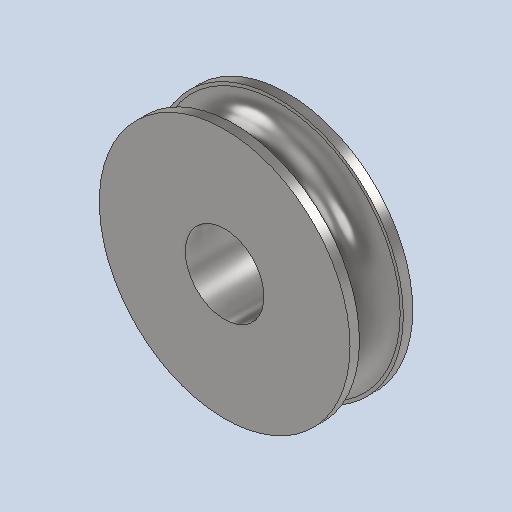
# Autodesk Inventor part: Biegerolle 62
Saved by Autodesk Inventor 2027.1 (Build 311270010, 270A)
## iProperties
Created: 2026-07-29
Part Number: Biegerolle 62
Material: Stahl, Legierung
Document SubType Name: Modeling
Designer: moest
Density: 7.73 g/cm^3
Appearance: Halbpoliert
Author: moest
Autodesk Inventor part; units mm, degrees
ref_plane "YZ Plane" through (0, 0, 0) normal (1, 0, 0) x (0, 1, 0)
ref_plane "XZ Plane" through (0, 0, 0) normal (0, 1, 0) x (-1, 0, 0)
ref_plane "XY Plane" through (0, 0, 0) normal (0, 0, 1) x (1, 0, 0)
sketch "Skizze1" plane through (0, 0, 0) normal (0, 0, 1) x (1, 0, 0)
  line L0 (0, 0) -> (0, 20)
  line L1 (0, 20) -> (40, 20)
  line L2 (40, 20) -> (40, 0)
  line L3 (40, 0) -> (0, 0)
  line L4 (20, 20) -> (20, 0)
  line L5 (0, 10) -> (31, 10)
  line L6 (31, 10) -> (31, 20)
  line L7 (31, 10) -> (31, 0)
  line L8 (40, 17) -> (0, 17)
  line L9 (0, 3) -> (40, 3)
  line L10 (31, 10) -> (39, 10)
  circle A0 centre (39, 10) radius 7
  point P0 (39, 3)
  point P1 (39, 17)
  dimension "d0" = 20
  dimension "d1" = 40
  dimension "d2" = 31
  dimension "d3" = 8
  constraints: 22 end point, 7 perpendicular, 7 point on line, 3 midpoint, 1 centre point, 1 coincident, 1 horizontal, 1 tangent, 1 vertical
  measures "d0" distance of L0.start L0.end
  measures "d1" distance of L0.end L1.end
  measures "d2" distance of L5.start L5.end
  measures "d3" distance of L5.end L10.end
revolve "Umdrehung1" add sketch "Skizze1" angle 360 about axis through (0, 0, 0) along (0, 1, 0) contours L0 L9 L4 L3 | L0 L5 L4 L9 | L4 L9 L7 L3 | L0 L8 L4 L5 | L4 L5 L7 L9 | L7 L9 L2 L3 | L0 L1 L4 L8 | L4 L8 L6 L5 | L7 L10 A0 L9 | L4 L1 L6 L8 | L6 L8 A0 L10 | L6 L1 L2 L8
sketch "Skizze2" plane through (0, 20, 0) normal (0, 1, 0) x (1, 0, 0)
  circle A0 centre (0, 0) radius 12.55
  dimension "d5" = 25.1
  constraints: 1 centre point, 1 coincident
  measures "d5" diameter of A0
extrude "Extrusion1" cut sketch "Skizze2" against normal blind 36.75
